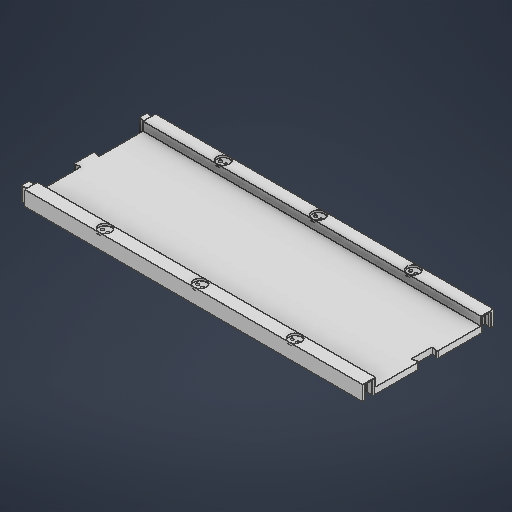
# Autodesk Inventor part: road
Saved by Autodesk Inventor 2026.4 (Build 304435000, 435)
## iProperties
Created: 2026-10-05
Part Number: road
Material: Generic
Document SubType Name: Modeling
Designer: LENOVO
Density: 1 g/cm^3
Appearance: Default
Author: LENOVO
Autodesk Inventor part; units mm, degrees
ref_plane "YZ Plane" through (0, 0, 0) normal (1, 0, 0) x (0, 1, 0)
ref_plane "XZ Plane" through (0, 0, 0) normal (0, 1, 0) x (-1, 0, 0)
ref_plane "XY Plane" through (0, 0, 0) normal (0, 0, 1) x (1, 0, 0)
sketch "Sketch1" plane through (0, 0, 0) normal (0, 1, 0) x (-1, 0, 0)
  line L0 (80, -25) -> (-80, -25)
  line L1 (-80, -25) -> (-80, 25)
  line L2 (-80, 25) -> (80, 25)
  line L3 (80, 25) -> (80, -25)
  line L4 (80, -25) -> (-80, 25) construction
  line L5 (-80, -25) -> (80, 25) construction
  point P0 (0, 0)
  dimension "d0" = 160
  dimension "d1" = 50
  constraints: 12 end point, 2 midpoint, 2 parallel, 1 horizontal, 1 perpendicular
  measures "d0" distance of L1.end L2.end
  measures "d1" distance of L0.end L1.end
extrude "Extrusion1" add sketch "Sketch1" along normal blind 2
sketch "Sketch2" plane through (0, 0, 0) normal (0, -1, 0) x (1, 0, 0)
  line L0 (-80, 25) -> (80, 25) projected
  line L1 (-80, -25) -> (-80, 25) projected
  line L2 (80, -25) -> (-80, -25) projected
  line L3 (80, 25) -> (80, -25) projected
  line L4 (-80, 25) -> (80, 25)
  line L5 (80, 25) -> (80, 31)
  line L6 (80, 31) -> (-80, 31)
  line L7 (-80, 31) -> (-80, 25)
  line L8 (-80, 0) -> (80, 0)
  line L9 (-80, -25) -> (80, -25)
  line L10 (80, -25) -> (80, -31)
  line L11 (80, -31) -> (-80, -31)
  line L12 (-80, -31) -> (-80, -25)
  point P0 (0, 0)
  dimension "d4" = 6
  dimension "d5" = 6
  constraints: 18 end point, 4 parallel, 2 horizontal, 2 midpoint, 2 perpendicular
  measures "d4" distance of L5.end L4.end
  measures "d5" distance of L9.end L10.end
extrude "Extrusion2" add sketch "Sketch2" against normal blind 6 contours L7 L6 L5 L0 | L2 L10 L11 L12
sketch "Sketch3" plane through (0, 0, 0) normal (0, -1, 0) x (1, 0, 0)
  line L0 (-80, 31) -> (-80, -31) projected
  line L1 (-80, -31) -> (80, -31) projected
  line L2 (80, -31) -> (80, 31) projected
  line L3 (80, 31) -> (-80, 31) projected
  line L4 (-80, 25) -> (80, 25) projected
  line L5 (80, 25) -> (80, -25) projected
  line L6 (80, -25) -> (-80, -25) projected
  line L7 (-80, -25) -> (-80, 25) projected
  line L8 (-77, 5) -> (-83, 5)
  line L9 (-83, 5) -> (-83, -5)
  line L10 (-83, -5) -> (-77, -5)
  line L11 (-77, -5) -> (-77, 5)
  line L12 (-77, 5) -> (-83, -5) construction
  line L13 (-83, 5) -> (-77, -5) construction
  line L14 (-80, 31) -> (-80, 25)
  line L15 (-77, 30) -> (-83, 30)
  line L16 (-83, 30) -> (-83, 26)
  line L17 (-83, 26) -> (-77, 26)
  line L18 (-77, 26) -> (-77, 30)
  line L19 (-77, 30) -> (-83, 26) construction
  line L20 (-83, 30) -> (-77, 26) construction
  line L21 (-83, 5) -> (-80, 4.1962)
  line L22 (-83, 5) -> (-79.8942, 5) construction
  line L23 (0, 0) -> (-80, 0)
  line L24 (-83, -5) -> (-80, -4.1962)
  line L25 (-83, 30) -> (-80, 29.1962)
  line L26 (-80, 31) -> (-80, -31) projected
  line L27 (-83, 30) -> (-79.8942, 30) construction
  line L28 (-80, -31) -> (-80, -25)
  line L29 (-77, -30) -> (-83, -30)
  line L30 (-83, -30) -> (-83, -26)
  line L31 (-83, -26) -> (-77, -26)
  line L32 (-77, -26) -> (-77, -30)
  line L33 (-77, -30) -> (-83, -26) construction
  line L34 (-83, -30) -> (-77, -26) construction
  line L35 (-83, -30) -> (-80, -29.1962)
  line L36 (-83, -30) -> (-79.8942, -30) construction
  line L37 (0, 31) -> (0, -31)
  line L38 (80, 31) -> (80, -31)
  line L39 (80, -25) -> (80, 25)
  line L40 (77, 5) -> (83, 5)
  line L41 (83, 5) -> (83, -5)
  line L42 (83, -5) -> (77, -5)
  line L43 (77, -5) -> (77, 5)
  line L44 (77, 5) -> (83, -5) construction
  line L45 (83, 5) -> (77, -5) construction
  line L46 (80, 31) -> (80, 25)
  line L47 (77, 30) -> (83, 30)
  line L48 (83, 30) -> (83, 26)
  line L49 (83, 26) -> (77, 26)
  line L50 (77, 26) -> (77, 30)
  line L51 (77, 30) -> (83, 26) construction
  line L52 (83, 30) -> (77, 26) construction
  line L53 (83, 5) -> (80, 4.1962)
  line L54 (83, 5) -> (79.8942, 5) construction
  line L55 (83, -5) -> (80, -4.1962)
  line L56 (83, 30) -> (80, 29.1962)
  line L57 (80, 31) -> (80, -31)
  line L58 (83, 30) -> (79.8942, 30) construction
  line L59 (83, -26) -> (77, -26)
  line L60 (77, -30) -> (83, -30)
  line L61 (83, -30) -> (83, -26)
  line L62 (77, -26) -> (77, -30)
  line L63 (77, -30) -> (83, -26) construction
  line L64 (83, -30) -> (80, -29.1962)
  line L65 (83, -30) -> (79.8942, -30) construction
  line L66 (80, -31) -> (80, -25)
  line L67 (83, -30) -> (77, -26) construction
  line L68 (77, 5) -> (80, 4.1962)
  line L69 (77, 5) -> (80.1058, 5) construction
  line L70 (77, 5) -> (77, -5)
  line L71 (83, 5) -> (77, 5)
  line L72 (83, 5) -> (77, -5) construction
  line L73 (77, 5) -> (83, -5) construction
  line L74 (77, -5) -> (83, -5)
  line L75 (77, -26) -> (83, -26)
  line L76 (77, -5) -> (80, -4.1962)
  line L77 (77, -30) -> (80, -29.1962)
  line L78 (83, -30) -> (77, -26) construction
  line L79 (77, -30) -> (83, -26) construction
  line L80 (77, -30) -> (80.1058, -30) construction
  line L81 (83, -30) -> (77, -30)
  line L82 (83, 30) -> (77, 30)
  line L83 (77, 30) -> (77, 26)
  line L84 (77, 30) -> (80.1058, 30) construction
  line L85 (77, 30) -> (80, 29.1962)
  line L86 (77, 26) -> (83, 26)
  line L87 (77, 30) -> (83, 26) construction
  line L88 (83, 30) -> (77, 26) construction
  line L89 (77, -30) -> (77, -26)
  point P0 (-80, 28)
  point P1 (-80, -28)
  point P2 (80, 0)
  point P3 (80, 28)
  point P4 (80, -28)
  point P5 (-80, -26)
  point P6 (-80, 26)
  dimension "d8" = 6
  dimension "d9" = 10
  dimension "d10" = 6
  dimension "d11" = 4
  dimension "d12" = 15
  dimension "d13" = 15
  constraints: 160 end point, 45 symmetric about line, 8 midpoint, 5 horizontal, 4 parallel, 2 equal length, 2 perpendicular, 2 point on line, 1 collinear, 6 other
  measures "d8" distance of L10.end L9.end
  measures "d9" distance of L9.end L8.end
  measures "d10" distance of L17.end L16.end
  measures "d11" distance of L16.end L15.end
  measures "d12" angle of L21 L22
  measures "d13" angle of L25 L27
extrude "Extrusion3" add sketch "Sketch3" against normal blind 2 contours L0 L24 L9 L21 | L17 L16 L25 L0 | L0 L35 L30 L31
sketch "Sketch4" plane through (0, 0, 0) normal (0, -1, 0) x (1, 0, 0)
  line L0 (-80, 31) -> (-80, 29.1962) projected
  line L1 (-80, 29.1962) -> (-83, 30) projected
  line L2 (-83, 30) -> (-83, 26) projected
  line L3 (-83, 26) -> (-80, 26) projected
  line L4 (-80, 26) -> (-80, 4.1962) projected
  line L5 (-80, 4.1962) -> (-83, 5) projected
  line L6 (-83, 5) -> (-83, -5) projected
  line L7 (-83, -5) -> (-80, -4.1962) projected
  line L8 (-80, -4.1962) -> (-80, -26) projected
  line L9 (-80, -26) -> (-83, -26) projected
  line L10 (-83, -26) -> (-83, -30) projected
  line L11 (-83, -30) -> (-80, -29.1962) projected
  line L12 (-80, -29.1962) -> (-80, -31) projected
  line L13 (-80, -31) -> (80, -31) projected
  line L14 (80, -31) -> (80, 31) projected
  line L15 (80, 31) -> (-80, 31) projected
  line L16 (0, 31) -> (0, -31)
  line L17 (80, 31) -> (80, 29.1962)
  line L18 (80, 29.1962) -> (83, 30)
  line L19 (83, 30) -> (83, 26)
  line L20 (83, 26) -> (80, 26)
  line L21 (80, 26) -> (80, 4.1962)
  line L22 (80, 4.1962) -> (83, 5)
  line L23 (83, 5) -> (83, -5)
  line L24 (83, -5) -> (80, -4.1962)
  line L25 (80, -4.1962) -> (80, -26)
  line L26 (80, -26) -> (83, -26)
  line L27 (83, -26) -> (83, -30)
  line L28 (83, -30) -> (80, -29.1962)
  line L29 (80, -29.1962) -> (80, -31)
  line L30 (77, -26) -> (77, -30)
  line L31 (77, -30) -> (80, -29.1962)
  line L32 (80, -26) -> (77, -26)
  line L33 (77, 5) -> (77, -5)
  line L34 (77, -5) -> (80, -4.1962)
  line L35 (80, 4.1962) -> (77, 5)
  line L36 (77, 30) -> (77, 26)
  line L37 (77, 26) -> (80, 26)
  line L38 (80, 29.1962) -> (77, 30)
  point P0 (0, 0)
  point P1 (-194.9783, -4.2235)
  point P2 (-194.9783, -1.0273)
  point P3 (-194.9783, 20.7765)
  point P4 (-194.9783, 29.1688)
  point P5 (-194.9783, 50.9727)
  point P6 (-194.9783, 54.1688)
  constraints: 46 end point, 18 symmetric about line, 2 midpoint
extrude "Extrusion4" cut sketch "Sketch4" against normal blind 2 contours L14 L37 L36 L38 | L31 L30 L32 L14 | L14 L34 L33 L35
sketch "Sketch5" plane through (0, 6, 0) normal (0, 1, 0) x (1, 0, 0)
  line L0 (-80, 31) -> (80, 31) projected
  line L1 (0, 31) -> (0, 25)
  line L2 (80, 25) -> (-80, 25) projected
  circle A0 centre (0, 28) radius 3
  point P0 (0, 0)
  dimension "d28" = 6
  constraints: 3 midpoint, 2 end point, 1 centre point
  measures "d28" diameter of A0
extrude "Extrusion5" cut sketch "Sketch5" against normal blind 1
sketch "Sketch6" plane through (0, 5, -28) normal (0, 1, 0) x (0, 0, 1)
  circle A0 centre (0, 1.27) radius 0.75
  arc A1 (-3, 0) -> (3, 0) centre (0, 0) ccw projected
  line L0 (-3, 0) -> (3, 0)
  circle A2 centre (0, -1.27) radius 0.75
  point P0 (28, 0)
  dimension "d29" = 1.5
  dimension "d30" = 1.27
  constraints: 2 centre point, 2 end point, 2 point on circle, 1 horizontal, 1 symmetric about line, 2 other
  measures "d29" diameter of A0
  measures "d30" distance of point (0, 0) A0.centre
extrude "Extrusion6" cut sketch "Sketch6" against normal blind 5 contours A0 | A2
pattern_linear "Rectangular Pattern1" count 2 spacing 45 along (-1, 0, 0) count 2 spacing 45 along (1, 0, 0) of "Extrusion5", "Extrusion6"
pattern_linear "Rectangular Pattern2" count 2 spacing 56 along (0, 0, 1) of "Extrusion5", "Extrusion6", "Rectangular Pattern1"
fillet "Fillet1" radius 0.5 12 edges at (80, 1, -29.1962) (80, 1, -26) (80, 1, -4.1962) (80, 1, 4.1962) (80, 1, 26) (80, 1, 29.1962) (-83, 1, 5) (-83, 1, -5) (-83, 1, 26) (-83, 1, 30) (-83, 1, -30) (-83, 1, -26)
sketch "Sketch7" plane through (0, 0, 0) normal (0, -1, 0) x (1, 0, 0)
  arc A0 (-82.5, -26) -> (-83, -26.5) centre (-82.5, -26.5) ccw projected
  line L0 (-83, -26.5) -> (-83, -29.3484) projected
  arc A1 (-83, -29.3484) -> (-82.3706, -29.8314) centre (-82.5, -29.3484) ccw projected
  line L1 (-82.3706, -29.8314) -> (-80, -29.1962) projected
  line L2 (-80, -29.1962) -> (-80, -31) projected
  line L3 (-80, -31) -> (80, -31) projected
  line L4 (80, -31) -> (80, -29.8478) projected
  arc A2 (80, -29.8478) -> (79.3706, -29.3648) centre (79.5, -29.8478) ccw projected
  line L5 (79.3706, -29.3648) -> (77, -30) projected
  line L6 (77, -30) -> (77, -26) projected
  line L7 (77, -26) -> (79.5, -26) projected
  arc A3 (79.5, -26) -> (80, -25.5) centre (79.5, -25.5) ccw projected
  line L8 (80, -25.5) -> (80, -4.8478) projected
  arc A4 (80, -4.8478) -> (79.3706, -4.3648) centre (79.5, -4.8478) ccw projected
  line L9 (79.3706, -4.3648) -> (77, -5) projected
  line L10 (77, -5) -> (77, 5) projected
  line L11 (77, 5) -> (79.3706, 4.3648) projected
  arc A5 (79.3706, 4.3648) -> (80, 4.8478) centre (79.5, 4.8478) ccw projected
  line L12 (80, 4.8478) -> (80, 25.5) projected
  arc A6 (80, 25.5) -> (79.5, 26) centre (79.5, 25.5) ccw projected
  line L13 (79.5, 26) -> (77, 26) projected
  line L14 (77, 26) -> (77, 30) projected
  line L15 (77, 30) -> (79.3706, 29.3648) projected
  arc A7 (79.3706, 29.3648) -> (80, 29.8478) centre (79.5, 29.8478) ccw projected
  line L16 (80, 29.8478) -> (80, 31) projected
  line L17 (80, 31) -> (-80, 31) projected
  line L18 (-80, 31) -> (-80, 29.1962) projected
  line L19 (-80, 29.1962) -> (-82.3706, 29.8314) projected
  arc A8 (-82.3706, 29.8314) -> (-83, 29.3484) centre (-82.5, 29.3484) ccw projected
  line L20 (-83, 29.3484) -> (-83, 26.5) projected
  arc A9 (-83, 26.5) -> (-82.5, 26) centre (-82.5, 26.5) ccw projected
  line L21 (-82.5, 26) -> (-80, 26) projected
  line L22 (-80, 26) -> (-80, 4.1962) projected
  line L23 (-80, 4.1962) -> (-82.3706, 4.8314) projected
  arc A10 (-82.3706, 4.8314) -> (-83, 4.3484) centre (-82.5, 4.3484) ccw projected
  line L24 (-83, 4.3484) -> (-83, -4.3484) projected
  arc A11 (-83, -4.3484) -> (-82.3706, -4.8314) centre (-82.5, -4.3484) ccw projected
  line L25 (-82.3706, -4.8314) -> (-80, -4.1962) projected
  line L26 (-80, -4.1962) -> (-80, -26) projected
  line L27 (-80, -26) -> (-82.5, -26) projected
  circle A12 centre (46.27, 28) radius 0.75 projected
  circle A13 centre (43.73, 28) radius 0.75 projected
  circle A14 centre (-43.73, 28) radius 0.75 projected
  circle A15 centre (-46.27, 28) radius 0.75 projected
  circle A16 centre (1.27, 28) radius 0.75 projected
  circle A17 centre (-1.27, 28) radius 0.75 projected
  circle A18 centre (46.27, -28) radius 0.75 projected
  circle A19 centre (43.73, -28) radius 0.75 projected
  circle A20 centre (-43.73, -28) radius 0.75 projected
  circle A21 centre (-46.27, -28) radius 0.75 projected
  circle A22 centre (1.27, -28) radius 0.75 projected
  circle A23 centre (-1.27, -28) radius 0.75 projected
  point P0 (0, 0)
extrude "Extrusion7" add sketch "Sketch7" along normal blind 1
sketch "Sketch8" plane through (0, 2, 0) normal (0, 1, 0) x (1, 0, 0)
  arc A0 (-83, 26.5) -> (-82.5, 26) centre (-82.5, 26.5) ccw projected
  line L0 (-82.5, 26) -> (-80, 26) projected
  line L1 (-80, 29.1962) -> (-80, 26) projected
  line L2 (-80, 29.1962) -> (-82.3706, 29.8314) projected
  arc A1 (-82.3706, 29.8314) -> (-83, 29.3484) centre (-82.5, 29.3484) ccw projected
  line L3 (-83, 29.3484) -> (-83, 26.5) projected
  arc A2 (-83, -29.3484) -> (-82.3706, -29.8314) centre (-82.5, -29.3484) ccw projected
  line L4 (-82.3706, -29.8314) -> (-80, -29.1962) projected
  line L5 (-80, -26) -> (-80, -29.1962) projected
  line L6 (-80, -26) -> (-82.5, -26) projected
  arc A3 (-82.5, -26) -> (-83, -26.5) centre (-82.5, -26.5) ccw projected
  line L7 (-83, -26.5) -> (-83, -29.3484) projected
  point P0 (0, 0)
extrude "Extrusion8" add sketch "Sketch8" along normal blind 3.5
sketch "Sketch9" plane through (0, 2, 0) normal (0, -1, 0) x (1, 0, 0)
  line L0 (80, 29.8478) -> (80, 25.5) projected
  arc A0 (79.3706, 29.3648) -> (80, 29.8478) centre (79.5, 29.8478) ccw projected
  line L1 (77, 30) -> (79.3706, 29.3648) projected
  line L2 (77, 26) -> (77, 30) projected
  line L3 (79.5, 26) -> (77, 26) projected
  arc A1 (80, 25.5) -> (79.5, 26) centre (79.5, 25.5) ccw projected
  line L4 (80, -25.5) -> (80, -29.8478) projected
  arc A2 (79.5, -26) -> (80, -25.5) centre (79.5, -25.5) ccw projected
  line L5 (77, -26) -> (79.5, -26) projected
  line L6 (77, -30) -> (77, -26) projected
  line L7 (79.3706, -29.3648) -> (77, -30) projected
  arc A3 (80, -29.8478) -> (79.3706, -29.3648) centre (79.5, -29.8478) ccw projected
  point P0 (0, 0)
extrude "Extrusion9" cut sketch "Sketch9" against normal blind 3.5
body "Solid1"
